Autodesk Fusion 360 part; units mm, degrees
(part 5 of 7)
sketch "Thread envelope sketch (18)" plane through (0, 0, 29) normal (0, 0, 1) x (1, 0, 0) in component "REFERENCE rear T nut 011"
  circle A0 centre (32, 228) radius 2.6
  dimension "d1862" = 32
  dimension "d1863" = 228
  dimension "d1864" = 5.2
  measures "d1862" horizontal distance of origin A0.centre
  measures "d1863" vertical distance of origin A0.centre
  measures "d1864" diameter of A0
extrude "Thread envelope'''''''''''''''''" cut sketch "Thread envelope sketch (18)" along normal blind 4 bodies 81 in component "REFERENCE rear join screw 011"
extrude "Extrude2'''''''''''''''''" cut sketch "Thread envelope sketch (18)" along normal blind 4 bodies 82 in component "REFERENCE rear T nut 011"
ref_plane "WorkPlane1" through (0, 0, 35) normal (0, 0, 1) x (1, 0, 0) in component "METAL rear splice plate 11"
sketch "Rear rail join plate sketch (5)" plane through (0, 0, 35) normal (0, 0, 1) x (1, 0, 0) in component "METAL rear splice plate 11"
  line L0 (92, 220) -> (148, 220)
  line L1 (148, 220) -> (148, 236)
  line L2 (148, 236) -> (92, 236)
  line L3 (92, 236) -> (92, 220)
  dimension "d1871" = 92
  dimension "d1872" = 220
  dimension "d1873" = 56
  dimension "d1874" = 16
  constraint horizontal L0
  constraint vertical L1
  constraint horizontal L2
  constraint vertical L3
  measures "d1871" horizontal distance of origin L0.start
  measures "d1872" vertical distance of origin L0.start
  measures "d1873" horizontal distance of L0.start L0.end
  measures "d1874" vertical distance of L0.end L1.end
extrude "Rear rail join plate''''" add sketch "Rear rail join plate sketch (5)" along normal blind 3 separate body makes body 83 in component "METAL rear splice plate 11"
ref_plane "WorkPlane2" through (0, 0, 35) normal (0, 0, 1) x (1, 0, 0) in component "METAL rear splice plate 11"
sketch "M5 clearance sketch (14)" plane through (0, 0, 35) normal (0, 0, 1) x (1, 0, 0) in component "METAL rear splice plate 11"
  circle A0 centre (100, 228) radius 2.75
  dimension "d1879" = 100
  dimension "d1880" = 228
  dimension "d1881" = 5.5
  measures "d1879" horizontal distance of origin A0.centre
  measures "d1880" vertical distance of origin A0.centre
  measures "d1881" diameter of A0
extrude "M5 clearance'''''''''''''" cut sketch "M5 clearance sketch (14)" along normal blind 3 bodies 83 in component "METAL rear splice plate 11"
ref_plane "WorkPlane1" through (0, 0, 38) normal (0, 0, 1) x (1, 0, 0) in component "REFERENCE rear join screw 110"
sketch "Nominal head sketch (10)" plane through (0, 0, 38) normal (0, 0, 1) x (1, 0, 0) in component "REFERENCE rear join screw 110"
  circle A0 centre (100, 228) radius 4.75
  dimension "d1886" = 100
  dimension "d1887" = 228
  dimension "d1888" = 9.5
  measures "d1886" horizontal distance of origin A0.centre
  measures "d1887" vertical distance of origin A0.centre
  measures "d1888" diameter of A0
extrude "Nominal head'''''''''" add sketch "Nominal head sketch (10)" along normal blind 3 separate body makes body 84 in component "REFERENCE rear join screw 110"
ref_plane "WorkPlane2" through (0, 0, 38) normal (0, 0, 1) x (1, 0, 0) in component "REFERENCE rear join screw 110"
sketch "M5x8 nominal shank sketch (10)" plane through (0, 0, 38) normal (0, 0, 1) x (1, 0, 0) in component "REFERENCE rear join screw 110"
  circle A0 centre (100, 228) radius 2.5
  dimension "d1893" = 100
  dimension "d1894" = 228
  dimension "d1895" = 5
  measures "d1893" horizontal distance of origin A0.centre
  measures "d1894" vertical distance of origin A0.centre
  measures "d1895" diameter of A0
extrude "M5x8 nominal shank'''''''''" add sketch "M5x8 nominal shank sketch (10)" against normal blind 8 bodies 84 in component "REFERENCE rear join screw 110"
ref_plane "WorkPlane1" through (0, 0, 29) normal (0, 0, 1) x (1, 0, 0) in component "REFERENCE rear T nut 110"
sketch "T nut envelope sketch (19)" plane through (0, 0, 29) normal (0, 0, 1) x (1, 0, 0) in component "REFERENCE rear T nut 110"
  line L0 (95.2, 223.2) -> (104.8, 223.2)
  line L1 (104.8, 223.2) -> (104.8, 232.8)
  line L2 (104.8, 232.8) -> (95.2, 232.8)
  line L3 (95.2, 232.8) -> (95.2, 223.2)
  dimension "d1900" = 95.2
  dimension "d1901" = 223.2
  dimension "d1902" = 9.6
  dimension "d1903" = 9.6
  constraint horizontal L0
  constraint vertical L1
  constraint horizontal L2
  constraint vertical L3
  measures "d1900" horizontal distance of origin L0.start
  measures "d1901" vertical distance of origin L0.start
  measures "d1902" horizontal distance of L0.start L0.end
  measures "d1903" vertical distance of L0.end L1.end
extrude "T nut envelope''''''''''''''''''" add sketch "T nut envelope sketch (19)" along normal blind 4 separate body makes body 85 in component "REFERENCE rear T nut 110"
ref_plane "WorkPlane2" through (0, 0, 29) normal (0, 0, 1) x (1, 0, 0) in component "REFERENCE rear T nut 110"
sketch "Thread envelope sketch (19)" plane through (0, 0, 29) normal (0, 0, 1) x (1, 0, 0) in component "REFERENCE rear T nut 110"
  circle A0 centre (100, 228) radius 2.6
  dimension "d1908" = 100
  dimension "d1909" = 228
  dimension "d1910" = 5.2
  measures "d1908" horizontal distance of origin A0.centre
  measures "d1909" vertical distance of origin A0.centre
  measures "d1910" diameter of A0
extrude "Thread envelope''''''''''''''''''" cut sketch "Thread envelope sketch (19)" along normal blind 4 bodies 84 in component "REFERENCE rear join screw 110"
extrude "Extrude2''''''''''''''''''" cut sketch "Thread envelope sketch (19)" along normal blind 4 bodies 85 in component "REFERENCE rear T nut 110"
ref_plane "WorkPlane3" through (0, 0, 35) normal (0, 0, 1) x (1, 0, 0) in component "METAL rear splice plate 11"
sketch "M5 clearance sketch (1) (5)" plane through (0, 0, 35) normal (0, 0, 1) x (1, 0, 0) in component "METAL rear splice plate 11"
  circle A0 centre (120, 228) radius 2.75
  dimension "d1917" = 120
  dimension "d1918" = 228
  dimension "d1919" = 5.5
  measures "d1917" horizontal distance of origin A0.centre
  measures "d1918" vertical distance of origin A0.centre
  measures "d1919" diameter of A0
extrude "M5 clearance (1)''''" cut sketch "M5 clearance sketch (1) (5)" along normal blind 3 bodies 83 in component "METAL rear splice plate 11"
ref_plane "WorkPlane1" through (0, 0, 38) normal (0, 0, 1) x (1, 0, 0) in component "REFERENCE rear join screw 111"
sketch "Nominal head sketch (11)" plane through (0, 0, 38) normal (0, 0, 1) x (1, 0, 0) in component "REFERENCE rear join screw 111"
  circle A0 centre (120, 228) radius 4.75
  dimension "d1924" = 120
  dimension "d1925" = 228
  dimension "d1926" = 9.5
  measures "d1924" horizontal distance of origin A0.centre
  measures "d1925" vertical distance of origin A0.centre
  measures "d1926" diameter of A0
extrude "Nominal head''''''''''" add sketch "Nominal head sketch (11)" along normal blind 3 separate body makes body 86 in component "REFERENCE rear join screw 111"
ref_plane "WorkPlane2" through (0, 0, 38) normal (0, 0, 1) x (1, 0, 0) in component "REFERENCE rear join screw 111"
sketch "M5x8 nominal shank sketch (11)" plane through (0, 0, 38) normal (0, 0, 1) x (1, 0, 0) in component "REFERENCE rear join screw 111"
  circle A0 centre (120, 228) radius 2.5
  dimension "d1931" = 120
  dimension "d1932" = 228
  dimension "d1933" = 5
  measures "d1931" horizontal distance of origin A0.centre
  measures "d1932" vertical distance of origin A0.centre
  measures "d1933" diameter of A0
extrude "M5x8 nominal shank''''''''''" add sketch "M5x8 nominal shank sketch (11)" against normal blind 8 bodies 86 in component "REFERENCE rear join screw 111"
ref_plane "WorkPlane1" through (0, 0, 29) normal (0, 0, 1) x (1, 0, 0) in component "REFERENCE rear T nut 111"
sketch "T nut envelope sketch (20)" plane through (0, 0, 29) normal (0, 0, 1) x (1, 0, 0) in component "REFERENCE rear T nut 111"
  line L0 (115.2, 223.2) -> (124.8, 223.2)
  line L1 (124.8, 223.2) -> (124.8, 232.8)
  line L2 (124.8, 232.8) -> (115.2, 232.8)
  line L3 (115.2, 232.8) -> (115.2, 223.2)
  dimension "d1938" = 115.2
  dimension "d1939" = 223.2
  dimension "d1940" = 9.6
  dimension "d1941" = 9.6
  constraint horizontal L0
  constraint vertical L1
  constraint horizontal L2
  constraint vertical L3
  measures "d1938" horizontal distance of origin L0.start
  measures "d1939" vertical distance of origin L0.start
  measures "d1940" horizontal distance of L0.start L0.end
  measures "d1941" vertical distance of L0.end L1.end
extrude "T nut envelope'''''''''''''''''''" add sketch "T nut envelope sketch (20)" along normal blind 4 separate body makes body 87 in component "REFERENCE rear T nut 111"
ref_plane "WorkPlane2" through (0, 0, 29) normal (0, 0, 1) x (1, 0, 0) in component "REFERENCE rear T nut 111"
sketch "Thread envelope sketch (20)" plane through (0, 0, 29) normal (0, 0, 1) x (1, 0, 0) in component "REFERENCE rear T nut 111"
  circle A0 centre (120, 228) radius 2.6
  dimension "d1946" = 120
  dimension "d1947" = 228
  dimension "d1948" = 5.2
  measures "d1946" horizontal distance of origin A0.centre
  measures "d1947" vertical distance of origin A0.centre
  measures "d1948" diameter of A0
extrude "Thread envelope'''''''''''''''''''" cut sketch "Thread envelope sketch (20)" along normal blind 4 bodies 86 in component "REFERENCE rear join screw 111"
extrude "Extrude2'''''''''''''''''''" cut sketch "Thread envelope sketch (20)" along normal blind 4 bodies 87 in component "REFERENCE rear T nut 111"
ref_plane "WorkPlane4" through (0, 0, 35) normal (0, 0, 1) x (1, 0, 0) in component "METAL rear splice plate 11"
sketch "M5 clearance sketch (2) (3)" plane through (0, 0, 35) normal (0, 0, 1) x (1, 0, 0) in component "METAL rear splice plate 11"
  circle A0 centre (140, 228) radius 2.75
  dimension "d1955" = 140
  dimension "d1956" = 228
  dimension "d1957" = 5.5
  measures "d1955" horizontal distance of origin A0.centre
  measures "d1956" vertical distance of origin A0.centre
  measures "d1957" diameter of A0
extrude "M5 clearance (2)'" cut sketch "M5 clearance sketch (2) (3)" along normal blind 3 bodies 83 in component "METAL rear splice plate 11"
ref_plane "WorkPlane1" through (0, 0, 38) normal (0, 0, 1) x (1, 0, 0) in component "REFERENCE rear join screw 112"
sketch "Nominal head sketch (12)" plane through (0, 0, 38) normal (0, 0, 1) x (1, 0, 0) in component "REFERENCE rear join screw 112"
  circle A0 centre (140, 228) radius 4.75
  dimension "d1962" = 140
  dimension "d1963" = 228
  dimension "d1964" = 9.5
  measures "d1962" horizontal distance of origin A0.centre
  measures "d1963" vertical distance of origin A0.centre
  measures "d1964" diameter of A0
extrude "Nominal head'''''''''''" add sketch "Nominal head sketch (12)" along normal blind 3 separate body makes body 88 in component "REFERENCE rear join screw 112"
ref_plane "WorkPlane2" through (0, 0, 38) normal (0, 0, 1) x (1, 0, 0) in component "REFERENCE rear join screw 112"
sketch "M5x8 nominal shank sketch (12)" plane through (0, 0, 38) normal (0, 0, 1) x (1, 0, 0) in component "REFERENCE rear join screw 112"
  circle A0 centre (140, 228) radius 2.5
  dimension "d1969" = 140
  dimension "d1970" = 228
  dimension "d1971" = 5
  measures "d1969" horizontal distance of origin A0.centre
  measures "d1970" vertical distance of origin A0.centre
  measures "d1971" diameter of A0
extrude "M5x8 nominal shank'''''''''''" add sketch "M5x8 nominal shank sketch (12)" against normal blind 8 bodies 88 in component "REFERENCE rear join screw 112"
ref_plane "WorkPlane1" through (0, 0, 29) normal (0, 0, 1) x (1, 0, 0) in component "REFERENCE rear T nut 112"
sketch "T nut envelope sketch (21)" plane through (0, 0, 29) normal (0, 0, 1) x (1, 0, 0) in component "REFERENCE rear T nut 112"
  line L0 (135.2, 223.2) -> (144.8, 223.2)
  line L1 (144.8, 223.2) -> (144.8, 232.8)
  line L2 (144.8, 232.8) -> (135.2, 232.8)
  line L3 (135.2, 232.8) -> (135.2, 223.2)
  dimension "d1976" = 135.2
  dimension "d1977" = 223.2
  dimension "d1978" = 9.6
  dimension "d1979" = 9.6
  constraint horizontal L0
  constraint vertical L1
  constraint horizontal L2
  constraint vertical L3
  measures "d1976" horizontal distance of origin L0.start
  measures "d1977" vertical distance of origin L0.start
  measures "d1978" horizontal distance of L0.start L0.end
  measures "d1979" vertical distance of L0.end L1.end
extrude "T nut envelope''''''''''''''''''''" add sketch "T nut envelope sketch (21)" along normal blind 4 separate body makes body 89 in component "REFERENCE rear T nut 112"
ref_plane "WorkPlane2" through (0, 0, 29) normal (0, 0, 1) x (1, 0, 0) in component "REFERENCE rear T nut 112"
sketch "Thread envelope sketch (21)" plane through (0, 0, 29) normal (0, 0, 1) x (1, 0, 0) in component "REFERENCE rear T nut 112"
  circle A0 centre (140, 228) radius 2.6
  dimension "d1984" = 140
  dimension "d1985" = 228
  dimension "d1986" = 5.2
  measures "d1984" horizontal distance of origin A0.centre
  measures "d1985" vertical distance of origin A0.centre
  measures "d1986" diameter of A0
extrude "Thread envelope''''''''''''''''''''" cut sketch "Thread envelope sketch (21)" along normal blind 4 bodies 88 in component "REFERENCE rear join screw 112"
extrude "Extrude2''''''''''''''''''''" cut sketch "Thread envelope sketch (21)" along normal blind 4 bodies 89 in component "REFERENCE rear T nut 112"
ref_plane "WorkPlane1" through (0, 0, 35) normal (0, 0, 1) x (1, 0, 0) in component "METAL rear splice plate 21"
sketch "Rear rail join plate sketch (6)" plane through (0, 0, 35) normal (0, 0, 1) x (1, 0, 0) in component "METAL rear splice plate 21"
  line L0 (200, 220) -> (236, 220)
  line L1 (236, 220) -> (236, 236)
  line L2 (236, 236) -> (200, 236)
  line L3 (200, 236) -> (200, 220)
  dimension "d1993" = 200
  dimension "d1994" = 220
  dimension "d1995" = 36
  dimension "d1996" = 16
  constraint horizontal L0
  constraint vertical L1
  constraint horizontal L2
  constraint vertical L3
  measures "d1993" horizontal distance of origin L0.start
  measures "d1994" vertical distance of origin L0.start
  measures "d1995" horizontal distance of L0.start L0.end
  measures "d1996" vertical distance of L0.end L1.end
extrude "Rear rail join plate'''''" add sketch "Rear rail join plate sketch (6)" along normal blind 3 separate body makes body 90 in component "METAL rear splice plate 21"
ref_plane "WorkPlane2" through (0, 0, 35) normal (0, 0, 1) x (1, 0, 0) in component "METAL rear splice plate 21"
sketch "M5 clearance sketch (15)" plane through (0, 0, 35) normal (0, 0, 1) x (1, 0, 0) in component "METAL rear splice plate 21"
  circle A0 centre (208, 228) radius 2.75
  dimension "d2001" = 208
  dimension "d2002" = 228
  dimension "d2003" = 5.5
  measures "d2001" horizontal distance of origin A0.centre
  measures "d2002" vertical distance of origin A0.centre
  measures "d2003" diameter of A0
extrude "M5 clearance''''''''''''''" cut sketch "M5 clearance sketch (15)" along normal blind 3 bodies 90 in component "METAL rear splice plate 21"
ref_plane "WorkPlane1" through (0, 0, 38) normal (0, 0, 1) x (1, 0, 0) in component "REFERENCE rear join screw 210"
sketch "Nominal head sketch (13)" plane through (0, 0, 38) normal (0, 0, 1) x (1, 0, 0) in component "REFERENCE rear join screw 210"
  circle A0 centre (208, 228) radius 4.75
  dimension "d2008" = 208
  dimension "d2009" = 228
  dimension "d2010" = 9.5
  measures "d2008" horizontal distance of origin A0.centre
  measures "d2009" vertical distance of origin A0.centre
  measures "d2010" diameter of A0
extrude "Nominal head''''''''''''" add sketch "Nominal head sketch (13)" along normal blind 3 separate body makes body 91 in component "REFERENCE rear join screw 210"
ref_plane "WorkPlane2" through (0, 0, 38) normal (0, 0, 1) x (1, 0, 0) in component "REFERENCE rear join screw 210"
sketch "M5x8 nominal shank sketch (13)" plane through (0, 0, 38) normal (0, 0, 1) x (1, 0, 0) in component "REFERENCE rear join screw 210"
  circle A0 centre (208, 228) radius 2.5
  dimension "d2015" = 208
  dimension "d2016" = 228
  dimension "d2017" = 5
  measures "d2015" horizontal distance of origin A0.centre
  measures "d2016" vertical distance of origin A0.centre
  measures "d2017" diameter of A0
extrude "M5x8 nominal shank''''''''''''" add sketch "M5x8 nominal shank sketch (13)" against normal blind 8 bodies 91 in component "REFERENCE rear join screw 210"
ref_plane "WorkPlane1" through (0, 0, 29) normal (0, 0, 1) x (1, 0, 0) in component "REFERENCE rear T nut 210"
sketch "T nut envelope sketch (22)" plane through (0, 0, 29) normal (0, 0, 1) x (1, 0, 0) in component "REFERENCE rear T nut 210"
  line L0 (203.2, 223.2) -> (212.8, 223.2)
  line L1 (212.8, 223.2) -> (212.8, 232.8)
  line L2 (212.8, 232.8) -> (203.2, 232.8)
  line L3 (203.2, 232.8) -> (203.2, 223.2)
  dimension "d2022" = 203.2
  dimension "d2023" = 223.2
  dimension "d2024" = 9.6
  dimension "d2025" = 9.6
  constraint horizontal L0
  constraint vertical L1
  constraint horizontal L2
  constraint vertical L3
  measures "d2022" horizontal distance of origin L0.start
  measures "d2023" vertical distance of origin L0.start
  measures "d2024" horizontal distance of L0.start L0.end
  measures "d2025" vertical distance of L0.end L1.end
extrude "T nut envelope'''''''''''''''''''''" add sketch "T nut envelope sketch (22)" along normal blind 4 separate body makes body 92 in component "REFERENCE rear T nut 210"
ref_plane "WorkPlane2" through (0, 0, 29) normal (0, 0, 1) x (1, 0, 0) in component "REFERENCE rear T nut 210"
sketch "Thread envelope sketch (22)" plane through (0, 0, 29) normal (0, 0, 1) x (1, 0, 0) in component "REFERENCE rear T nut 210"
  circle A0 centre (208, 228) radius 2.6
  dimension "d2030" = 208
  dimension "d2031" = 228
  dimension "d2032" = 5.2
  measures "d2030" horizontal distance of origin A0.centre
  measures "d2031" vertical distance of origin A0.centre
  measures "d2032" diameter of A0
extrude "Thread envelope'''''''''''''''''''''" cut sketch "Thread envelope sketch (22)" along normal blind 4 bodies 91 in component "REFERENCE rear join screw 210"
extrude "Extrude2'''''''''''''''''''''" cut sketch "Thread envelope sketch (22)" along normal blind 4 bodies 92 in component "REFERENCE rear T nut 210"
ref_plane "WorkPlane3" through (0, 0, 35) normal (0, 0, 1) x (1, 0, 0) in component "METAL rear splice plate 21"
sketch "M5 clearance sketch (1) (6)" plane through (0, 0, 35) normal (0, 0, 1) x (1, 0, 0) in component "METAL rear splice plate 21"
  circle A0 centre (228, 228) radius 2.75
  dimension "d2039" = 228
  dimension "d2040" = 228
  dimension "d2041" = 5.5
  measures "d2039" horizontal distance of origin A0.centre
  measures "d2040" vertical distance of origin A0.centre
  measures "d2041" diameter of A0
extrude "M5 clearance (1)'''''" cut sketch "M5 clearance sketch (1) (6)" along normal blind 3 bodies 90 in component "METAL rear splice plate 21"
ref_plane "WorkPlane1" through (0, 0, 38) normal (0, 0, 1) x (1, 0, 0) in component "REFERENCE rear join screw 211"
sketch "Nominal head sketch (14)" plane through (0, 0, 38) normal (0, 0, 1) x (1, 0, 0) in component "REFERENCE rear join screw 211"
  circle A0 centre (228, 228) radius 4.75
  dimension "d2046" = 228
  dimension "d2047" = 228
  dimension "d2048" = 9.5
  measures "d2046" horizontal distance of origin A0.centre
  measures "d2047" vertical distance of origin A0.centre
  measures "d2048" diameter of A0
extrude "Nominal head'''''''''''''" add sketch "Nominal head sketch (14)" along normal blind 3 separate body makes body 93 in component "REFERENCE rear join screw 211"
ref_plane "WorkPlane2" through (0, 0, 38) normal (0, 0, 1) x (1, 0, 0) in component "REFERENCE rear join screw 211"
sketch "M5x8 nominal shank sketch (14)" plane through (0, 0, 38) normal (0, 0, 1) x (1, 0, 0) in component "REFERENCE rear join screw 211"
  circle A0 centre (228, 228) radius 2.5
  dimension "d2053" = 228
  dimension "d2054" = 228
  dimension "d2055" = 5
  measures "d2053" horizontal distance of origin A0.centre
  measures "d2054" vertical distance of origin A0.centre
  measures "d2055" diameter of A0
extrude "M5x8 nominal shank'''''''''''''" add sketch "M5x8 nominal shank sketch (14)" against normal blind 8 bodies 93 in component "REFERENCE rear join screw 211"
ref_plane "WorkPlane1" through (0, 0, 29) normal (0, 0, 1) x (1, 0, 0) in component "REFERENCE rear T nut 211"
sketch "T nut envelope sketch (23)" plane through (0, 0, 29) normal (0, 0, 1) x (1, 0, 0) in component "REFERENCE rear T nut 211"
  line L0 (223.2, 223.2) -> (232.8, 223.2)
  line L1 (232.8, 223.2) -> (232.8, 232.8)
  line L2 (232.8, 232.8) -> (223.2, 232.8)
  line L3 (223.2, 232.8) -> (223.2, 223.2)
  dimension "d2060" = 223.2
  dimension "d2061" = 223.2
  dimension "d2062" = 9.6
  dimension "d2063" = 9.6
  constraint horizontal L0
  constraint vertical L1
  constraint horizontal L2
  constraint vertical L3
  measures "d2060" horizontal distance of origin L0.start
  measures "d2061" vertical distance of origin L0.start
  measures "d2062" horizontal distance of L0.start L0.end
  measures "d2063" vertical distance of L0.end L1.end
extrude "T nut envelope''''''''''''''''''''''" add sketch "T nut envelope sketch (23)" along normal blind 4 separate body makes body 94 in component "REFERENCE rear T nut 211"
ref_plane "WorkPlane2" through (0, 0, 29) normal (0, 0, 1) x (1, 0, 0) in component "REFERENCE rear T nut 211"
sketch "Thread envelope sketch (23)" plane through (0, 0, 29) normal (0, 0, 1) x (1, 0, 0) in component "REFERENCE rear T nut 211"
  circle A0 centre (228, 228) radius 2.6
  dimension "d2068" = 228
  dimension "d2069" = 228
  dimension "d2070" = 5.2
  measures "d2068" horizontal distance of origin A0.centre
  measures "d2069" vertical distance of origin A0.centre
  measures "d2070" diameter of A0
extrude "Thread envelope''''''''''''''''''''''" cut sketch "Thread envelope sketch (23)" along normal blind 4 bodies 93 in component "REFERENCE rear join screw 211"
extrude "Extrude2''''''''''''''''''''''" cut sketch "Thread envelope sketch (23)" along normal blind 4 bodies 94 in component "REFERENCE rear T nut 211"
ref_plane "WorkPlane1" through (0, 0, 35) normal (0, 0, 1) x (1, 0, 0) in component "METAL wall standoff 00 - welded or machined"
sketch "Rail pad sketch" plane through (0, 0, 35) normal (0, 0, 1) x (1, 0, 0) in component "METAL wall standoff 00 - welded or machined"
  line L0 (2, 45) -> (22, 45)
  line L1 (22, 45) -> (22, 75)
  line L2 (22, 75) -> (2, 75)
  line L3 (2, 75) -> (2, 45)
  dimension "d2079" = 2
  dimension "d2080" = 45
  dimension "d2081" = 20
  dimension "d2082" = 30
  constraint horizontal L0
  constraint vertical L1
  constraint horizontal L2
  constraint vertical L3
  measures "d2079" horizontal distance of origin L0.start
  measures "d2080" vertical distance of origin L0.start
  measures "d2081" horizontal distance of L0.start L0.end
  measures "d2082" vertical distance of L0.end L1.end
extrude "Rail pad" add sketch "Rail pad sketch" along normal blind 3 separate body makes body 95 in component "METAL wall standoff 00 - welded or machined"
ref_plane "WorkPlane2" through (0, 0, 38) normal (0, 0, 1) x (1, 0, 0) in component "METAL wall standoff 00 - welded or machined"
sketch "Standoff web sketch" plane through (0, 0, 38) normal (0, 0, 1) x (1, 0, 0) in component "METAL wall standoff 00 - welded or machined"
  line L0 (19, 45) -> (22, 45)
  line L1 (22, 45) -> (22, 75)
  line L2 (22, 75) -> (19, 75)
  line L3 (19, 75) -> (19, 45)
  dimension "d2087" = 19
  dimension "d2088" = 45
  dimension "d2089" = 3
  dimension "d2090" = 30
  constraint horizontal L0
  constraint vertical L1
  constraint horizontal L2
  constraint vertical L3
  measures "d2087" horizontal distance of origin L0.start
  measures "d2088" vertical distance of origin L0.start
  measures "d2089" horizontal distance of L0.start L0.end
  measures "d2090" vertical distance of L0.end L1.end
extrude "Standoff web" add sketch "Standoff web sketch" along normal blind 4 bodies 95 in component "METAL wall standoff 00 - welded or machined"
ref_plane "WorkPlane3" through (0, 0, 42) normal (0, 0, 1) x (1, 0, 0) in component "METAL wall standoff 00 - welded or machined"
sketch "Wall foot sketch" plane through (0, 0, 42) normal (0, 0, 1) x (1, 0, 0) in component "METAL wall standoff 00 - welded or machined"
  line L0 (19, 45) -> (44, 45)
  line L1 (44, 45) -> (44, 75)
  line L2 (44, 75) -> (19, 75)
  line L3 (19, 75) -> (19, 45)
  dimension "d2095" = 19
  dimension "d2096" = 45
  dimension "d2097" = 25
  dimension "d2098" = 30
  constraint horizontal L0
  constraint vertical L1
  constraint horizontal L2
  constraint vertical L3
  measures "d2095" horizontal distance of origin L0.start
  measures "d2096" vertical distance of origin L0.start
  measures "d2097" horizontal distance of L0.start L0.end
  measures "d2098" vertical distance of L0.end L1.end
extrude "Wall foot" add sketch "Wall foot sketch" along normal blind 3 bodies 95 in component "METAL wall standoff 00 - welded or machined"
ref_plane "WorkPlane4" through (0, 0, 42) normal (0, 0, 1) x (1, 0, 0) in component "METAL wall standoff 00 - welded or machined"
sketch "Wall anchor interface sketch" plane through (0, 0, 42) normal (0, 0, 1) x (1, 0, 0) in component "METAL wall standoff 00 - welded or machined"
  circle A0 centre (34, 60) radius 3.25
  dimension "d2103" = 34
  dimension "d2104" = 60
  dimension "d2105" = 6.5
  measures "d2103" horizontal distance of origin A0.centre
  measures "d2104" vertical distance of origin A0.centre
  measures "d2105" diameter of A0
extrude "Wall anchor interface" cut sketch "Wall anchor interface sketch" along normal blind 3 bodies 95 in component "METAL wall standoff 00 - welded or machined"
ref_plane "WorkPlane5" through (0, 0, 35) normal (0, 0, 1) x (1, 0, 0) in component "METAL wall standoff 00 - welded or machined"
sketch "Rail attachment clearance sketch" plane through (0, 0, 35) normal (0, 0, 1) x (1, 0, 0) in component "METAL wall standoff 00 - welded or machined"
  circle A0 centre (12, 52) radius 2.75
  dimension "d2110" = 12
  dimension "d2111" = 52
  dimension "d2112" = 5.5
  measures "d2110" horizontal distance of origin A0.centre
  measures "d2111" vertical distance of origin A0.centre
  measures "d2112" diameter of A0
extrude "Rail attachment clearance" cut sketch "Rail attachment clearance sketch" along normal blind 3 bodies 95 in component "METAL wall standoff 00 - welded or machined"
ref_plane "WorkPlane1" through (0, 0, 38) normal (0, 0, 1) x (1, 0, 0) in component "REFERENCE wall bracket M5x8 000"
sketch "Head sketch" plane through (0, 0, 38) normal (0, 0, 1) x (1, 0, 0) in component "REFERENCE wall bracket M5x8 000"
  circle A0 centre (12, 52) radius 4.75
  dimension "d2117" = 12
  dimension "d2118" = 52
  dimension "d2119" = 9.5
  measures "d2117" horizontal distance of origin A0.centre
  measures "d2118" vertical distance of origin A0.centre
  measures "d2119" diameter of A0
extrude "Head" add sketch "Head sketch" along normal blind 3 separate body makes body 96 in component "REFERENCE wall bracket M5x8 000"
ref_plane "WorkPlane2" through (0, 0, 38) normal (0, 0, 1) x (1, 0, 0) in component "REFERENCE wall bracket M5x8 000"
sketch "Shank sketch" plane through (0, 0, 38) normal (0, 0, 1) x (1, 0, 0) in component "REFERENCE wall bracket M5x8 000"
  circle A0 centre (12, 52) radius 2.5
  dimension "d2124" = 12
  dimension "d2125" = 52
  dimension "d2126" = 5
  measures "d2124" horizontal distance of origin A0.centre
  measures "d2125" vertical distance of origin A0.centre
  measures "d2126" diameter of A0
extrude "Shank" add sketch "Shank sketch" against normal blind 8 bodies 96 in component "REFERENCE wall bracket M5x8 000"
ref_plane "WorkPlane1" through (0, 0, 29) normal (0, 0, 1) x (1, 0, 0) in component "REFERENCE wall bracket T nut 000"
sketch "Nut sketch" plane through (0, 0, 29) normal (0, 0, 1) x (1, 0, 0) in component "REFERENCE wall bracket T nut 000"
  line L0 (7.2, 47.2) -> (16.8, 47.2)
  line L1 (16.8, 47.2) -> (16.8, 56.8)
  line L2 (16.8, 56.8) -> (7.2, 56.8)
  line L3 (7.2, 56.8) -> (7.2, 47.2)
  dimension "d2131" = 7.2
  dimension "d2132" = 47.2
  dimension "d2133" = 9.6
  dimension "d2134" = 9.6
  constraint horizontal L0
  constraint vertical L1
  constraint horizontal L2
  constraint vertical L3
  measures "d2131" horizontal distance of origin L0.start
  measures "d2132" vertical distance of origin L0.start
  measures "d2133" horizontal distance of L0.start L0.end
  measures "d2134" vertical distance of L0.end L1.end
extrude "Nut" add sketch "Nut sketch" along normal blind 4 separate body makes body 97 in component "REFERENCE wall bracket T nut 000"
ref_plane "WorkPlane2" through (0, 0, 29) normal (0, 0, 1) x (1, 0, 0) in component "REFERENCE wall bracket T nut 000"
sketch "Thread envelope sketch (24)" plane through (0, 0, 29) normal (0, 0, 1) x (1, 0, 0) in component "REFERENCE wall bracket T nut 000"
  circle A0 centre (12, 52) radius 2.6
  dimension "d2139" = 12
  dimension "d2140" = 52
  dimension "d2141" = 5.2
  measures "d2139" horizontal distance of origin A0.centre
  measures "d2140" vertical distance of origin A0.centre
  measures "d2141" diameter of A0
extrude "Thread envelope'''''''''''''''''''''''" cut sketch "Thread envelope sketch (24)" along normal blind 4 bodies 96 in component "REFERENCE wall bracket M5x8 000"
extrude "Extrude2'''''''''''''''''''''''" cut sketch "Thread envelope sketch (24)" along normal blind 4 bodies 97 in component "REFERENCE wall bracket T nut 000"
ref_plane "WorkPlane6" through (0, 0, 35) normal (0, 0, 1) x (1, 0, 0) in component "METAL wall standoff 00 - welded or machined"
sketch "Rail attachment clearance sketch (1)" plane through (0, 0, 35) normal (0, 0, 1) x (1, 0, 0) in component "METAL wall standoff 00 - welded or machined"
  circle A0 centre (12, 68) radius 2.75
  dimension "d2148" = 12
  dimension "d2149" = 68
  dimension "d2150" = 5.5
  measures "d2148" horizontal distance of origin A0.centre
  measures "d2149" vertical distance of origin A0.centre
  measures "d2150" diameter of A0
extrude "Rail attachment clearance (1)" cut sketch "Rail attachment clearance sketch (1)" along normal blind 3 bodies 95 in component "METAL wall standoff 00 - welded or machined"
ref_plane "WorkPlane1" through (0, 0, 38) normal (0, 0, 1) x (1, 0, 0) in component "REFERENCE wall bracket M5x8 001"
sketch "Head sketch (2)" plane through (0, 0, 38) normal (0, 0, 1) x (1, 0, 0) in component "REFERENCE wall bracket M5x8 001"
  circle A0 centre (12, 68) radius 4.75
  dimension "d2155" = 12
  dimension "d2156" = 68
  dimension "d2157" = 9.5
  measures "d2155" horizontal distance of origin A0.centre
  measures "d2156" vertical distance of origin A0.centre
  measures "d2157" diameter of A0
extrude "Head'" add sketch "Head sketch (2)" along normal blind 3 separate body makes body 98 in component "REFERENCE wall bracket M5x8 001"
ref_plane "WorkPlane2" through (0, 0, 38) normal (0, 0, 1) x (1, 0, 0) in component "REFERENCE wall bracket M5x8 001"
sketch "Shank sketch (2)" plane through (0, 0, 38) normal (0, 0, 1) x (1, 0, 0) in component "REFERENCE wall bracket M5x8 001"
  circle A0 centre (12, 68) radius 2.5
  dimension "d2162" = 12
  dimension "d2163" = 68
  dimension "d2164" = 5
  measures "d2162" horizontal distance of origin A0.centre
  measures "d2163" vertical distance of origin A0.centre
  measures "d2164" diameter of A0
extrude "Shank'" add sketch "Shank sketch (2)" against normal blind 8 bodies 98 in component "REFERENCE wall bracket M5x8 001"
ref_plane "WorkPlane1" through (0, 0, 29) normal (0, 0, 1) x (1, 0, 0) in component "REFERENCE wall bracket T nut 001"
sketch "Nut sketch (2)" plane through (0, 0, 29) normal (0, 0, 1) x (1, 0, 0) in component "REFERENCE wall bracket T nut 001"
  line L0 (7.2, 63.2) -> (16.8, 63.2)
  line L1 (16.8, 63.2) -> (16.8, 72.8)
  line L2 (16.8, 72.8) -> (7.2, 72.8)
  line L3 (7.2, 72.8) -> (7.2, 63.2)
  dimension "d2169" = 7.2
  dimension "d2170" = 63.2
  dimension "d2171" = 9.6
  dimension "d2172" = 9.6
  constraint horizontal L0
  constraint vertical L1
  constraint horizontal L2
  constraint vertical L3
  measures "d2169" horizontal distance of origin L0.start
  measures "d2170" vertical distance of origin L0.start
  measures "d2171" horizontal distance of L0.start L0.end
  measures "d2172" vertical distance of L0.end L1.end
extrude "Nut'" add sketch "Nut sketch (2)" along normal blind 4 separate body makes body 99 in component "REFERENCE wall bracket T nut 001"
ref_plane "WorkPlane2" through (0, 0, 29) normal (0, 0, 1) x (1, 0, 0) in component "REFERENCE wall bracket T nut 001"
sketch "Thread envelope sketch (25)" plane through (0, 0, 29) normal (0, 0, 1) x (1, 0, 0) in component "REFERENCE wall bracket T nut 001"
  circle A0 centre (12, 68) radius 2.6
  dimension "d2177" = 12
  dimension "d2178" = 68
  dimension "d2179" = 5.2
  measures "d2177" horizontal distance of origin A0.centre
  measures "d2178" vertical distance of origin A0.centre
  measures "d2179" diameter of A0
extrude "Thread envelope''''''''''''''''''''''''" cut sketch "Thread envelope sketch (25)" along normal blind 4 bodies 98 in component "REFERENCE wall bracket M5x8 001"
extrude "Extrude2''''''''''''''''''''''''" cut sketch "Thread envelope sketch (25)" along normal blind 4 bodies 99 in component "REFERENCE wall bracket T nut 001"
ref_plane "WorkPlane1" through (0, 0, 35) normal (0, 0, 1) x (1, 0, 0) in component "METAL wall standoff 01 - welded or machined"
sketch "Rail pad sketch (2)" plane through (0, 0, 35) normal (0, 0, 1) x (1, 0, 0) in component "METAL wall standoff 01 - welded or machined"
  line L0 (2, 165) -> (22, 165)
  line L1 (22, 165) -> (22, 195)
  line L2 (22, 195) -> (2, 195)
  line L3 (2, 195) -> (2, 165)
  dimension "d2186" = 2
  dimension "d2187" = 165
  dimension "d2188" = 20
  dimension "d2189" = 30
  constraint horizontal L0
  constraint vertical L1
  constraint horizontal L2
  constraint vertical L3
  measures "d2186" horizontal distance of origin L0.start
  measures "d2187" vertical distance of origin L0.start
  measures "d2188" horizontal distance of L0.start L0.end
  measures "d2189" vertical distance of L0.end L1.end
extrude "Rail pad'" add sketch "Rail pad sketch (2)" along normal blind 3 separate body makes body 100 in component "METAL wall standoff 01 - welded or machined"
ref_plane "WorkPlane2" through (0, 0, 38) normal (0, 0, 1) x (1, 0, 0) in component "METAL wall standoff 01 - welded or machined"
sketch "Standoff web sketch (2)" plane through (0, 0, 38) normal (0, 0, 1) x (1, 0, 0) in component "METAL wall standoff 01 - welded or machined"
  line L0 (19, 165) -> (22, 165)
  line L1 (22, 165) -> (22, 195)
  line L2 (22, 195) -> (19, 195)
  line L3 (19, 195) -> (19, 165)
  dimension "d2194" = 19
  dimension "d2195" = 165
  dimension "d2196" = 3
  dimension "d2197" = 30
  constraint horizontal L0
  constraint vertical L1
  constraint horizontal L2
  constraint vertical L3
  measures "d2194" horizontal distance of origin L0.start
  measures "d2195" vertical distance of origin L0.start
  measures "d2196" horizontal distance of L0.start L0.end
  measures "d2197" vertical distance of L0.end L1.end
extrude "Standoff web'" add sketch "Standoff web sketch (2)" along normal blind 4 bodies 100 in component "METAL wall standoff 01 - welded or machined"
ref_plane "WorkPlane3" through (0, 0, 42) normal (0, 0, 1) x (1, 0, 0) in component "METAL wall standoff 01 - welded or machined"
sketch "Wall foot sketch (2)" plane through (0, 0, 42) normal (0, 0, 1) x (1, 0, 0) in component "METAL wall standoff 01 - welded or machined"
  line L0 (19, 165) -> (44, 165)
  line L1 (44, 165) -> (44, 195)
  line L2 (44, 195) -> (19, 195)
  line L3 (19, 195) -> (19, 165)
  dimension "d2202" = 19
  dimension "d2203" = 165
  dimension "d2204" = 25
  dimension "d2205" = 30
  constraint horizontal L0
  constraint vertical L1
  constraint horizontal L2
  constraint vertical L3
  measures "d2202" horizontal distance of origin L0.start
  measures "d2203" vertical distance of origin L0.start
  measures "d2204" horizontal distance of L0.start L0.end
  measures "d2205" vertical distance of L0.end L1.end
extrude "Wall foot'" add sketch "Wall foot sketch (2)" along normal blind 3 bodies 100 in component "METAL wall standoff 01 - welded or machined"
ref_plane "WorkPlane4" through (0, 0, 42) normal (0, 0, 1) x (1, 0, 0) in component "METAL wall standoff 01 - welded or machined"
sketch "Wall anchor interface sketch (2)" plane through (0, 0, 42) normal (0, 0, 1) x (1, 0, 0) in component "METAL wall standoff 01 - welded or machined"
  circle A0 centre (34, 180) radius 3.25
  dimension "d2210" = 34
  dimension "d2211" = 180
  dimension "d2212" = 6.5
extrude "Wall anchor interface'" cut sketch "Wall anchor interface sketch (2)" along normal blind 3 bodies 100 in component "METAL wall standoff 01 - welded or machined"
ref_plane "WorkPlane5" through (0, 0, 35) normal (0, 0, 1) x (1, 0, 0) in component "METAL wall standoff 01 - welded or machined"
sketch "Rail attachment clearance sketch (2)" plane through (0, 0, 35) normal (0, 0, 1) x (1, 0, 0) in component "METAL wall standoff 01 - welded or machined"
  circle A0 centre (12, 172) radius 2.75
  dimension "d2217" = 12
  dimension "d2218" = 172
  dimension "d2219" = 5.5
  measures "d2217" horizontal distance of origin A0.centre
  measures "d2218" vertical distance of origin A0.centre
  measures "d2219" diameter of A0
extrude "Rail attachment clearance'" cut sketch "Rail attachment clearance sketch (2)" along normal blind 3 bodies 100 in component "METAL wall standoff 01 - welded or machined"
ref_plane "WorkPlane1" through (0, 0, 38) normal (0, 0, 1) x (1, 0, 0) in component "REFERENCE wall bracket M5x8 010"
sketch "Head sketch (3)" plane through (0, 0, 38) normal (0, 0, 1) x (1, 0, 0) in component "REFERENCE wall bracket M5x8 010"
  circle A0 centre (12, 172) radius 4.75
  dimension "d2224" = 12
  dimension "d2225" = 172
  dimension "d2226" = 9.5
  measures "d2224" horizontal distance of origin A0.centre
  measures "d2225" vertical distance of origin A0.centre
  measures "d2226" diameter of A0
extrude "Head''" add sketch "Head sketch (3)" along normal blind 3 separate body makes body 101 in component "REFERENCE wall bracket M5x8 010"
ref_plane "WorkPlane2" through (0, 0, 38) normal (0, 0, 1) x (1, 0, 0) in component "REFERENCE wall bracket M5x8 010"
sketch "Shank sketch (3)" plane through (0, 0, 38) normal (0, 0, 1) x (1, 0, 0) in component "REFERENCE wall bracket M5x8 010"
  circle A0 centre (12, 172) radius 2.5
  dimension "d2231" = 12
  dimension "d2232" = 172
  dimension "d2233" = 5
  measures "d2231" horizontal distance of origin A0.centre
  measures "d2232" vertical distance of origin A0.centre
  measures "d2233" diameter of A0
extrude "Shank''" add sketch "Shank sketch (3)" against normal blind 8 bodies 101 in component "REFERENCE wall bracket M5x8 010"
ref_plane "WorkPlane1" through (0, 0, 29) normal (0, 0, 1) x (1, 0, 0) in component "REFERENCE wall bracket T nut 010"
sketch "Nut sketch (3)" plane through (0, 0, 29) normal (0, 0, 1) x (1, 0, 0) in component "REFERENCE wall bracket T nut 010"
  line L0 (7.2, 167.2) -> (16.8, 167.2)
  line L1 (16.8, 167.2) -> (16.8, 176.8)
  line L2 (16.8, 176.8) -> (7.2, 176.8)
  line L3 (7.2, 176.8) -> (7.2, 167.2)
  dimension "d2238" = 7.2
  dimension "d2239" = 167.2
  dimension "d2240" = 9.6
  dimension "d2241" = 9.6
  constraint horizontal L0
  constraint vertical L1
  constraint horizontal L2
  constraint vertical L3
  measures "d2238" horizontal distance of origin L0.start
  measures "d2239" vertical distance of origin L0.start
  measures "d2240" horizontal distance of L0.start L0.end
  measures "d2241" vertical distance of L0.end L1.end
extrude "Nut''" add sketch "Nut sketch (3)" along normal blind 4 separate body makes body 102 in component "REFERENCE wall bracket T nut 010"
ref_plane "WorkPlane2" through (0, 0, 29) normal (0, 0, 1) x (1, 0, 0) in component "REFERENCE wall bracket T nut 010"
sketch "Thread envelope sketch (26)" plane through (0, 0, 29) normal (0, 0, 1) x (1, 0, 0) in component "REFERENCE wall bracket T nut 010"
  circle A0 centre (12, 172) radius 2.6
  dimension "d2246" = 12
  dimension "d2247" = 172
  dimension "d2248" = 5.2
  measures "d2246" horizontal distance of origin A0.centre
  measures "d2247" vertical distance of origin A0.centre
  measures "d2248" diameter of A0
extrude "Thread envelope'''''''''''''''''''''''''" cut sketch "Thread envelope sketch (26)" along normal blind 4 bodies 101 in component "REFERENCE wall bracket M5x8 010"
extrude "Extrude2'''''''''''''''''''''''''" cut sketch "Thread envelope sketch (26)" along normal blind 4 bodies 102 in component "REFERENCE wall bracket T nut 010"
ref_plane "WorkPlane6" through (0, 0, 35) normal (0, 0, 1) x (1, 0, 0) in component "METAL wall standoff 01 - welded or machined"
sketch "Rail attachment clearance sketch (1) (2)" plane through (0, 0, 35) normal (0, 0, 1) x (1, 0, 0) in component "METAL wall standoff 01 - welded or machined"
  circle A0 centre (12, 188) radius 2.75
  dimension "d2255" = 12
  dimension "d2256" = 188
  dimension "d2257" = 5.5
  measures "d2255" horizontal distance of origin A0.centre
  measures "d2256" vertical distance of origin A0.centre
  measures "d2257" diameter of A0
extrude "Rail attachment clearance (1)'" cut sketch "Rail attachment clearance sketch (1) (2)" along normal blind 3 bodies 100 in component "METAL wall standoff 01 - welded or machined"
ref_plane "WorkPlane1" through (0, 0, 38) normal (0, 0, 1) x (1, 0, 0) in component "REFERENCE wall bracket M5x8 011"
sketch "Head sketch (4)" plane through (0, 0, 38) normal (0, 0, 1) x (1, 0, 0) in component "REFERENCE wall bracket M5x8 011"
  circle A0 centre (12, 188) radius 4.75
  dimension "d2262" = 12
  dimension "d2263" = 188
  dimension "d2264" = 9.5
  measures "d2262" horizontal distance of origin A0.centre
  measures "d2263" vertical distance of origin A0.centre
  measures "d2264" diameter of A0
extrude "Head'''" add sketch "Head sketch (4)" along normal blind 3 separate body makes body 103 in component "REFERENCE wall bracket M5x8 011"
ref_plane "WorkPlane2" through (0, 0, 38) normal (0, 0, 1) x (1, 0, 0) in component "REFERENCE wall bracket M5x8 011"
sketch "Shank sketch (4)" plane through (0, 0, 38) normal (0, 0, 1) x (1, 0, 0) in component "REFERENCE wall bracket M5x8 011"
  circle A0 centre (12, 188) radius 2.5
  dimension "d2269" = 12
  dimension "d2270" = 188
  dimension "d2271" = 5
  measures "d2269" horizontal distance of origin A0.centre
  measures "d2270" vertical distance of origin A0.centre
  measures "d2271" diameter of A0
extrude "Shank'''" add sketch "Shank sketch (4)" against normal blind 8 bodies 103 in component "REFERENCE wall bracket M5x8 011"
ref_plane "WorkPlane1" through (0, 0, 29) normal (0, 0, 1) x (1, 0, 0) in component "REFERENCE wall bracket T nut 011"
sketch "Nut sketch (4)" plane through (0, 0, 29) normal (0, 0, 1) x (1, 0, 0) in component "REFERENCE wall bracket T nut 011"
  line L0 (7.2, 183.2) -> (16.8, 183.2)
  line L1 (16.8, 183.2) -> (16.8, 192.8)
  line L2 (16.8, 192.8) -> (7.2, 192.8)
  line L3 (7.2, 192.8) -> (7.2, 183.2)
  dimension "d2276" = 7.2
  dimension "d2277" = 183.2
  dimension "d2278" = 9.6
  dimension "d2279" = 9.6
  constraint horizontal L0
  constraint vertical L1
  constraint horizontal L2
  constraint vertical L3
  measures "d2276" horizontal distance of origin L0.start
  measures "d2277" vertical distance of origin L0.start
  measures "d2278" horizontal distance of L0.start L0.end
  measures "d2279" vertical distance of L0.end L1.end
extrude "Nut'''" add sketch "Nut sketch (4)" along normal blind 4 separate body makes body 104 in component "REFERENCE wall bracket T nut 011"
ref_plane "WorkPlane2" through (0, 0, 29) normal (0, 0, 1) x (1, 0, 0) in component "REFERENCE wall bracket T nut 011"
sketch "Thread envelope sketch (27)" plane through (0, 0, 29) normal (0, 0, 1) x (1, 0, 0) in component "REFERENCE wall bracket T nut 011"
  circle A0 centre (12, 188) radius 2.6
  dimension "d2284" = 12
  dimension "d2285" = 188
  dimension "d2286" = 5.2
  measures "d2284" horizontal distance of origin A0.centre
  measures "d2285" vertical distance of origin A0.centre
  measures "d2286" diameter of A0
extrude "Thread envelope''''''''''''''''''''''''''" cut sketch "Thread envelope sketch (27)" along normal blind 4 bodies 103 in component "REFERENCE wall bracket M5x8 011"
extrude "Extrude2''''''''''''''''''''''''''" cut sketch "Thread envelope sketch (27)" along normal blind 4 bodies 104 in component "REFERENCE wall bracket T nut 011"
ref_plane "WorkPlane1" through (0, 0, 35) normal (0, 0, 1) x (1, 0, 0) in component "METAL wall standoff 10 - welded or machined"
sketch "Rail pad sketch (3)" plane through (0, 0, 35) normal (0, 0, 1) x (1, 0, 0) in component "METAL wall standoff 10 - welded or machined"
  line L0 (218, 45) -> (238, 45)
  line L1 (238, 45) -> (238, 75)
  line L2 (238, 75) -> (218, 75)
  line L3 (218, 75) -> (218, 45)
  dimension "d2293" = 218
  dimension "d2294" = 45
  dimension "d2295" = 20
  dimension "d2296" = 30
  constraint horizontal L0
  constraint vertical L1
  constraint horizontal L2
  constraint vertical L3
  measures "d2293" horizontal distance of origin L0.start
  measures "d2294" vertical distance of origin L0.start
  measures "d2295" horizontal distance of L0.start L0.end
  measures "d2296" vertical distance of L0.end L1.end
extrude "Rail pad''" add sketch "Rail pad sketch (3)" along normal blind 3 separate body makes body 105 in component "METAL wall standoff 10 - welded or machined"
ref_plane "WorkPlane2" through (0, 0, 38) normal (0, 0, 1) x (1, 0, 0) in component "METAL wall standoff 10 - welded or machined"
sketch "Standoff web sketch (3)" plane through (0, 0, 38) normal (0, 0, 1) x (1, 0, 0) in component "METAL wall standoff 10 - welded or machined"
  line L0 (218, 45) -> (221, 45)
  line L1 (221, 45) -> (221, 75)
  line L2 (221, 75) -> (218, 75)
  line L3 (218, 75) -> (218, 45)
  dimension "d2301" = 218
  dimension "d2302" = 45
  dimension "d2303" = 3
  dimension "d2304" = 30
  constraint horizontal L0
  constraint vertical L1
  constraint horizontal L2
  constraint vertical L3
  measures "d2301" horizontal distance of origin L0.start
  measures "d2302" vertical distance of origin L0.start
  measures "d2303" horizontal distance of L0.start L0.end
  measures "d2304" vertical distance of L0.end L1.end
extrude "Standoff web''" add sketch "Standoff web sketch (3)" along normal blind 4 bodies 105 in component "METAL wall standoff 10 - welded or machined"
ref_plane "WorkPlane3" through (0, 0, 42) normal (0, 0, 1) x (1, 0, 0) in component "METAL wall standoff 10 - welded or machined"
sketch "Wall foot sketch (3)" plane through (0, 0, 42) normal (0, 0, 1) x (1, 0, 0) in component "METAL wall standoff 10 - welded or machined"
  line L0 (196, 45) -> (221, 45)
  line L1 (221, 45) -> (221, 75)
  line L2 (221, 75) -> (196, 75)
  line L3 (196, 75) -> (196, 45)
  dimension "d2309" = 196
  dimension "d2310" = 45
  dimension "d2311" = 25
  dimension "d2312" = 30
  constraint horizontal L0
  constraint vertical L1
  constraint horizontal L2
  constraint vertical L3
  measures "d2309" horizontal distance of origin L0.start
  measures "d2310" vertical distance of origin L0.start
  measures "d2311" horizontal distance of L0.start L0.end
  measures "d2312" vertical distance of L0.end L1.end
extrude "Wall foot''" add sketch "Wall foot sketch (3)" along normal blind 3 bodies 105 in component "METAL wall standoff 10 - welded or machined"
ref_plane "WorkPlane4" through (0, 0, 42) normal (0, 0, 1) x (1, 0, 0) in component "METAL wall standoff 10 - welded or machined"
sketch "Wall anchor interface sketch (3)" plane through (0, 0, 42) normal (0, 0, 1) x (1, 0, 0) in component "METAL wall standoff 10 - welded or machined"
  circle A0 centre (206, 60) radius 3.25
  dimension "d2317" = 206
  dimension "d2318" = 60
  dimension "d2319" = 6.5
  measures "d2317" horizontal distance of origin A0.centre
  measures "d2318" vertical distance of origin A0.centre
  measures "d2319" diameter of A0
extrude "Wall anchor interface''" cut sketch "Wall anchor interface sketch (3)" along normal blind 3 bodies 105 in component "METAL wall standoff 10 - welded or machined"
ref_plane "WorkPlane5" through (0, 0, 35) normal (0, 0, 1) x (1, 0, 0) in component "METAL wall standoff 10 - welded or machined"
sketch "Rail attachment clearance sketch (3)" plane through (0, 0, 35) normal (0, 0, 1) x (1, 0, 0) in component "METAL wall standoff 10 - welded or machined"
  circle A0 centre (228, 52) radius 2.75
  dimension "d2324" = 228
  dimension "d2325" = 52
  dimension "d2326" = 5.5
  measures "d2324" horizontal distance of origin A0.centre
  measures "d2325" vertical distance of origin A0.centre
  measures "d2326" diameter of A0
extrude "Rail attachment clearance''" cut sketch "Rail attachment clearance sketch (3)" along normal blind 3 bodies 105 in component "METAL wall standoff 10 - welded or machined"
ref_plane "WorkPlane1" through (0, 0, 38) normal (0, 0, 1) x (1, 0, 0) in component "REFERENCE wall bracket M5x8 100"
sketch "Head sketch (5)" plane through (0, 0, 38) normal (0, 0, 1) x (1, 0, 0) in component "REFERENCE wall bracket M5x8 100"
  circle A0 centre (228, 52) radius 4.75
  dimension "d2331" = 228
  dimension "d2332" = 52
  dimension "d2333" = 9.5
  measures "d2331" horizontal distance of origin A0.centre
  measures "d2332" vertical distance of origin A0.centre
  measures "d2333" diameter of A0
extrude "Head''''" add sketch "Head sketch (5)" along normal blind 3 separate body makes body 106 in component "REFERENCE wall bracket M5x8 100"